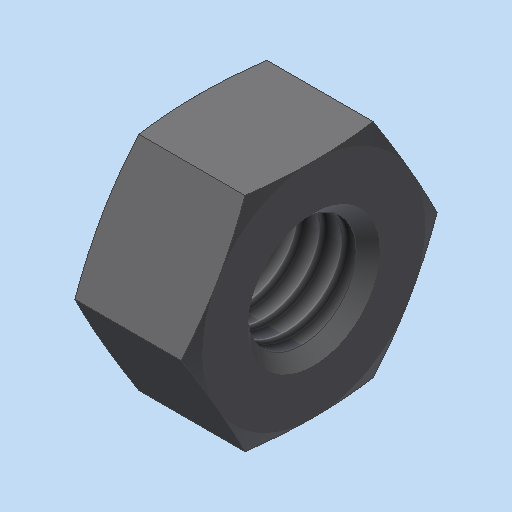
# Autodesk Inventor part: Sechskantmutter_ISO_4032___M6
Saved by Autodesk Inventor 2023.3 (Build 273359000, 359)
## iProperties
Shininess: 64.0
Length Units: 11269
Angle Units: 11279
Time Units: 11290
Mass Units: 11283
Length Display Precision: 3
Angle Display Precision: 2
Compacted: True
Part Number: Sechskantmutter_ISO_4032___M6
Document SubType Name: Modeling
Created: 2004-03-22
Material: xStahl_AnP_Dummymaterial
Description: =<RBPARTNOTITLE2>
Vendor: NORM8
Designer: S.Riedelsheimer
Manufacturer: Standard
Standards Organization: Custom
Density: 7.85 g/cm^3
Appearance: Stahl - normal AnP
Mass: 2.71393 g
Surface Area: 3.82294 cm^2
Volume: 0.345723 cm^3
Density: 0.0
Volumn: 0.0
Area: 0.0
PropertySet Name: Model Information
Control State: 0
Master: False
Checked Out: False
CNS_NB: Sechskantmutter ISO 4032 - M 6
CNS_NN: ISO 4032
CNS_NT: Sechskantmutter, Typ 1
CNS_NBSYN: Sechskantmutter ISO 4032 - $NENN.
CNS_LINA: Sechskantmutter ISO 4032 - M 6
CNS_NENN: M 6
CNS_D: 6.000
CNS_D1: 4.917
CNS_P: 1.000
CNS_M: 5.200
CNS_S: 10.000
CNS_KT: X
PSOL_IDENT_0: {C:\partsolutions8\data\23d-libs\bosch_bamberg\muttern\sechskantmuttern\din_iso_4032.prj},166 {M=Nen
PSOL_IDENT_1: ngewinde},{VTYP=3D},{NB=Sechskantmutter ISO 4032 - M 6},{NN=ISO 4032},{DATE=26.11.2003},{GEOMDATE=26
PSOL_IDENT_2: .11.2003},{VERSION=v2},{LINEID=70},{LINESUBID=-1},{WBVAR=}  {NB=Sechskantmutter ISO 4032 - M 6},{LIN
PSOL_IDENT_3: A=Sechskantmutter ISO 4032 - M 6},{KT=X},{IDNR=},{NENN=M 6},{D=6.000},{D1=4.917},{P=1.000},{M=5.200}
PSOL_IDENT_4: ,{S=10.000}
RBPARTNOTITLE1: Hexagon regular nuts (style 1)
RBPARTNOTITLE2: Sechskantmuttern (Typ 1)
RBDRAWINGMISSINGSPEC: --
AnP_Kategorie: 5
RBPARTMADEOF: ISO 4032 - M6 - 8.8 - verzinkt
Title: Sechskantmutter ISO 4032 - M 6
Author: S.Riedelsheimer
Keywords: =<RBPARTMADEOF>
Comments: =<RBSURFACE2>
Revision Number: 01
Autodesk Inventor part; units mm, degrees
sketch "Sketch_1" plane through (0, 0, 0) normal (0, 1, 0) x (-1, 0, 0)
  line L0 (0, 0) -> (-5.2, 0)
  line L1 (0, 5) -> (-2.6, 14.7033)
  line L2 (-2.6, 14.7033) -> (-5.2, 5)
  line L3 (-5.2, 5) -> (-5.2, 3)
  line L4 (-5.2, 3) -> (-4.6585, 2.4585)
  line L5 (-4.6585, 2.4585) -> (-0.5415, 2.4585)
  line L6 (-0.5415, 2.4585) -> (0, 3)
  line L7 (0, 3) -> (0, 5)
  constraints: 16 end point
revolve "Drehung1" add sketch "Sketch_1" angle 360 about axis through (0, 0, 0) along (-1, 0, 0)
thread "Gewinde1" size "M6x1" class "6H" standard "ANSI Metric M Profile" length 5.2
sketch "Sketch_2" plane through (0, 0, 0) normal (1, 0, 0) x (0, 1, 0)
  line L0 (-20, 20) -> (-20, -20)
  line L1 (-20, -20) -> (20, -20)
  line L2 (20, -20) -> (20, 20)
  line L3 (20, 20) -> (-20, 20)
  line L4 (-2.8868, 5) -> (-5.7735, 0)
  line L5 (-5.7735, 0) -> (-2.8868, -5)
  line L6 (-2.8868, -5) -> (2.8868, -5)
  line L7 (2.8868, -5) -> (5.7735, 0)
  line L8 (5.7735, 0) -> (2.8868, 5)
  line L9 (2.8868, 5) -> (-2.8868, 5)
  constraints: 20 end point
extrude "Extrusion1" cut sketch "Sketch_2" along normal mid plane 12.4
ref_plane "IP1_XY" through (0, 0, 0) normal (1, 0, 0) x (0, 0, -1)
ref_plane "IP1_YZ" through (0, 0, 0) normal (0, 0, -1) x (0, 1, 0)
ref_plane "IP2_XY" through (5.2, 0, 0) normal (1, 0, 0) x (0, 0, -1)
ref_plane "IP2_YZ" through (5.2, 0, 0) normal (0, 0, -1) x (0, 1, 0)
